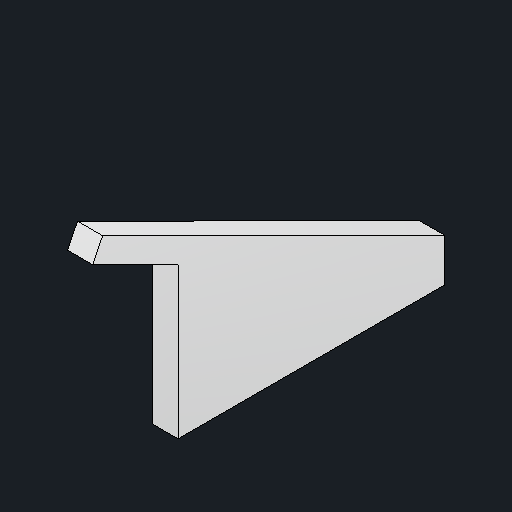
# Autodesk Inventor part: Echelle support side plate
Saved by Autodesk Inventor 2027.1 (Build 311270010, 270A)
## iProperties
Created: 2026-11-21
Part Number: Echelle support side plate
Material: Aluminum 6061
Description: Echelle support side plate; photo-based dimensional mockup, verify before fabrication
Document SubType Name: Modeling
Designer: queezz
Density: 2.7 g/cm^3
Appearance: Aluminum - Flat
Mass: 133.467 g
Surface Area: 137.076 cm^2
Volume: 49.4322 cm^3
Author: queezz
Autodesk Inventor part; units mm, degrees
ref_plane "YZ Plane" through (0, 0, 0) normal (1, 0, 0) x (0, 1, 0)
ref_plane "XZ Plane" through (0, 0, 0) normal (0, 1, 0) x (-1, 0, 0)
ref_plane "XY Plane" through (0, 0, 0) normal (0, 0, 1) x (1, 0, 0)
sketch "Side profile - straight lower cut without toe" plane through (0, 0, 0) normal (1, 0, 0) x (0, 1, 0)
  line L0 (10, 0) -> (27.186, 0)
  line L1 (27.186, 0) -> (94.999, 136.0118)
  line L2 (94.999, 136.0118) -> (87, 140)
  line L3 (87, 140) -> (70, 106)
  line L4 (70, 106) -> (10, 106)
  line L5 (10, 106) -> (10, 0)
  point P0 (0, 0)
  dimension "d26" = 10
  dimension "d27" = 27.186
  dimension "d28" = 94.999
  dimension "d29" = 136.0119
  dimension "d30" = 87
  dimension "d31" = 140
  dimension "d32" = 70
  dimension "d33" = 106
  dimension "d34" = 10
  dimension "d35" = 106
  constraints: 12 end point, 2 horizontal alignment, 1 other
  measures "d26" distance of point (0, 0) L0.start
  measures "d27" distance of point (0, 0) L0.end
  measures "d28" horizontal distance of point (0, 0) L1.end
  measures "d29" vertical distance of point (0, 0) L1.end
  measures "d30" horizontal distance of point (0, 0) L2.end
  measures "d31" vertical distance of point (0, 0) L2.end
  measures "d32" horizontal distance of point (0, 0) L3.end
  measures "d33" vertical distance of point (0, 0) L3.end
  measures "d34" horizontal distance of point (0, 0) L4.end
  measures "d35" vertical distance of point (0, 0) L4.end
extrude "Side plate stock" add sketch "Side profile - straight lower cut without toe" along normal blind 10
equation "\"d26\" = StockThickness"
equation "\"d30\" = ArmTip"
equation "\"d31\" = SupportHeight"
equation "\"d32\" = ArmRoot"
equation "\"d33\" = ArmHeight"
equation "\"d34\" = StockThickness"
equation "\"d35\" = ArmHeight"
equation "\"d36\" = StockThickness"
equation "\"StockThickness\" = 10"
equation "\"ArmTip\" = 87"
equation "\"SupportHeight\" = 140"
equation "\"ArmRoot\" = 70"
equation "\"ArmHeight\" = 106"
body "Solid3"
